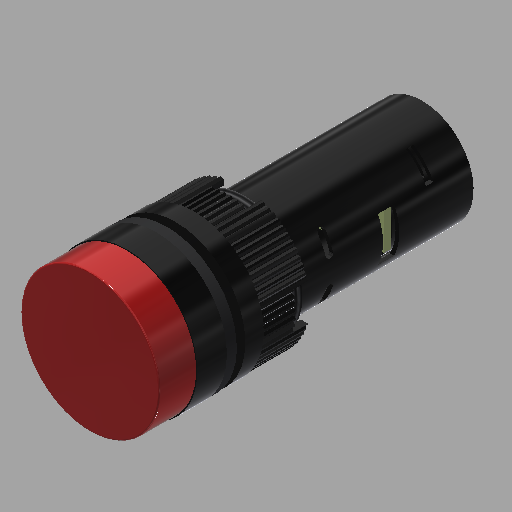
# Autodesk Inventor part: SINALEIRO VERMELHO
Saved by Autodesk Inventor 2022.2 (Build 262287030, 287C)
## iProperties
Created: 2020-08-06
Part Number: SINALEIRO VERMELHO
Material: Plástico, preto opaco
Document SubType Name: Modeling
Designer: Projeto
Density: 0.952 g/cm^3
Appearance: Transparente - Vermelho polido
Mass: 6.60714 g
Surface Area: 62.6153 cm^2
Volume: 6.94027 cm^3
Author: Projeto
Autodesk Inventor part; units mm, degrees
ref_plane "YZ Plane" through (0, 0, 0) normal (1, 0, 0) x (0, 1, 0)
ref_plane "XZ Plane" through (0, 0, 0) normal (0, 1, 0) x (-1, 0, 0)
ref_plane "XY Plane" through (0, 0, 0) normal (0, 0, 1) x (1, 0, 0)
sketch "Esboço1" plane through (0, 0, 0) normal (1, 0, 0) x (0, 1, 0)
  line L0 (0, 0) -> (9.2, 0)
  line L1 (9.4, -0.2) -> (9.4, -5)
  line L2 (9.4, -5) -> (9.55, -5)
  line L3 (9.55, -5) -> (9.55, -9)
  line L4 (9.55, -9) -> (9.5, -9)
  line L5 (9.5, -9) -> (9.5, -10.4)
  line L6 (9.5, -10.4) -> (7.9, -10.4)
  line L7 (7.9, -10.4) -> (7.9, -11.6)
  line L8 (7.9, -11.6) -> (9.45, -11.6)
  line L9 (9.45, -11.6) -> (9.45, -14.1)
  line L10 (9.45, -14.1) -> (9.3, -14.1)
  line L11 (9.3, -14.1) -> (9.3, -20.6)
  line L12 (7, -21.7) -> (7, -43.5)
  line L13 (7, -43.5) -> (6.975, -43.5)
  line L14 (6.975, -43.5) -> (6.975, -45)
  line L15 (6.975, -45) -> (0, -45)
  arc A0 (9.4, -0.2) -> (9.2, 0) centre (9.2, -0.2) ccw
  line L16 (8.35, -20.6) -> (8.35, -18.1)
  line L17 (8.35, -18.1) -> (7.9, -18.1)
  line L18 (7.9, -18.1) -> (7.9, -21.7)
  line L19 (9.3, -20.6) -> (8.35, -20.6)
  line L20 (7.9, -21.7) -> (7, -21.7)
  line L21 (0, -1.5) -> (7.7, -1.5)
  line L22 (7.7, -1.5) -> (7.7, -8.5)
  line L23 (7.7, -8.5) -> (7.35, -8.5)
  line L24 (7.35, -8.5) -> (7.35, -2)
  line L25 (7.35, -2) -> (0, -2)
  line L26 (0, -1.5) -> (0, 0)
  line L27 (0, -21.7) -> (6.5, -21.7)
  line L28 (6.5, -21.7) -> (6.5, -44.5)
  line L29 (6.5, -44.5) -> (6.4, -44.5)
  line L30 (6, -44.1) -> (6, -35)
  line L31 (6, -35) -> (0, -35)
  line L32 (0, 0) -> (0, -45) construction
  line L33 (0, -2) -> (0, -21.7)
  line L34 (0, -35) -> (0, -45)
  line L35 (6.4, -44.5) -> (6, -44.1)
  point P0 (6, -44.5)
  dimension "d8" = 45
  dimension "d9" = 5
  dimension "d10" = 4
  dimension "d11" = 1.4
  dimension "d12" = 1.2
  dimension "d13" = 2.5
  dimension "d15" = 1.5
  dimension "d16" = 0.2
  dimension "d25" = 6.5
  dimension "d26" = 2.5
  dimension "d28" = 1.5
  dimension "d30" = 3
  dimension "d31" = 6.5
  dimension "d32" = 12.7
  dimension "d62" = 14
  dimension "d63" = 13.95
  dimension "d64" = 15.8
  dimension "d65" = 16.7
  dimension "d66" = 18.6
  dimension "d67" = 18.9
  dimension "d68" = 15.8
  dimension "d69" = 19
  dimension "d70" = 19.1
  dimension "d71" = 18.8
  dimension "d72" = 15.4
  dimension "d73" = 14.7
  dimension "d74" = 0.5
  dimension "d75" = 0.5
  dimension "d76" = 12
  dimension "d77" = 10
  dimension "d78" = 0.4
  dimension "d79" = 0.4
  constraints: 72 end point, 30 perpendicular, 6 point on line, 3 vertical, 2 collinear, 2 horizontal, 2 point on circle, 2 tangent, 1 centre point, 1 horizontal alignment
  measures "d8" distance between parallel lines of L0 L15
  measures "d9" distance between parallel lines of L2 L0
  measures "d10" distance of L2.end L3.end
  measures "d11" distance between parallel lines of L4 L6
  measures "d12" distance between parallel lines of L8 L6
  measures "d13" distance of L8.end L9.end
  measures "d15" distance between parallel lines of L13 L15
  measures "d16" radius of A0
  measures "d25" distance between parallel lines of L19 L10
  measures "d26" distance between parallel lines of L17 L19
  measures "d28" distance between parallel lines of L21 L0
  measures "d30" distance between parallel lines of L2 L25
  measures "d31" distance between parallel lines of L23 L25
  measures "d32" distance between parallel lines of L20 L4
  measures "d62" diameter of L12 L32
  measures "d63" diameter of L14 L32
  measures "d64" diameter of L18 L32
  measures "d65" diameter of L16 L32
  measures "d66" diameter of L11 L32
  measures "d67" diameter of L9 L32
  measures "d68" diameter of L7 L32
  measures "d69" diameter of L5 L32
  measures "d70" diameter of L3 L32
  measures "d71" diameter of L1 L32
  measures "d72" diameter of L22 L32
  measures "d73" diameter of L24 L32
  measures "d74" distance between parallel lines of L28 L12
  measures "d75" distance between parallel lines of L15 L29
  measures "d76" diameter of L30 L32
  measures "d77" distance between parallel lines of L15 L31
  measures "d78" distance of L29.end point (6, -44.5)
  measures "d79" distance of L30.start point (6, -44.5)
revolve "Revolução1" add sketch "Esboço1" angle 360 about axis through (0, 0, 0) along (0, 0, -1)
sketch "Esboço3" plane through (0, 0, -20.6) normal (0, 0, -1) x (-1, 0, 0)
  circle A0 centre (0, 0) radius 9.3 projected
  circle A1 centre (0, 0) radius 8.35 projected
  line L0 (-8.9577, -2.5) -> (-7.967, -2.5)
  line L1 (-8.9577, 2.5) -> (-7.967, 2.5)
  line L2 (7.967, -2.5) -> (8.9577, -2.5)
  line L3 (7.967, 2.5) -> (8.9577, 2.5)
  line L4 (-2.5, 7.967) -> (-2.5, 8.9577)
  line L5 (2.5, 7.967) -> (2.5, 8.9577)
  line L6 (-2.5, -7.967) -> (-2.5, -8.9577)
  line L7 (2.5, -7.967) -> (2.5, -8.9577)
  dimension "d33" = 2.5
  dimension "d34" = 2.5
  dimension "d35" = 2.5
  dimension "d36" = 2.5
  constraints: 16 end point, 5 parallel, 2 horizontal, 2 horizontal alignment, 2 vertical alignment, 1 perpendicular, 18 other
  measures "d33" distance from line of point (0, 0) L0
  measures "d34" distance from line of point (0, 0) L1
  measures "d35" distance from line of point (0, 0) L6
  measures "d36" distance from line of point (0, 0) L7
extrude "Extrusão2" cut sketch "Esboço3" against normal blind 2 contours A0 L2 A1 L3 | L5 A1 L4 A0 | A0 L6 A1 L7 | L1 A1 L0 A0
sketch "Esboço4" plane through (8.9577, 2.5, -20.6) normal (0, 0, -1) x (-1, 0, 0)
  arc A0 (11.4577, 6.4577) -> (6.4577, 6.4577) centre (8.9577, -2.5) ccw construction
  line L0 (8.6624, 6.7953) -> (8.887, 6.5707)
  line L1 (9.0284, 6.5707) -> (9.253, 6.7953)
  line L2 (8.9577, 6.5) -> (8.9577, -2.5) construction
  arc A1 (9.253, 6.7953) -> (8.6624, 6.7953) centre (8.9577, -2.5) ccw
  arc A2 (8.887, 6.5707) -> (9.0284, 6.5707) centre (8.9577, 6.6414) ccw
  dimension "d39" = 90
  dimension "d40" = 45
  dimension "d41" = 9
  dimension "d47" = 0.1
  constraints: 6 end point, 6 point on circle, 2 centre point, 2 point on line, 2 tangent, 1 concentric, 1 vertical, 1 vertical alignment
  measures "d39" angle of L1 L0
  measures "d40" angle of L2 L0
  measures "d41" distance of L2.start L2.end
  measures "d47" radius of A2
extrude "Extrusão3" cut sketch "Esboço4" against normal up to surface (6.5 mm away)
pattern_circular "Padrão circular1" count 70 over 360 about axis through (0, 0, -10) along (0, 0, 1) of "Extrusão3"
thread "Rosca1" size "M16x0.75" class "6g" standard "ANSI Metric M Profile" full length
chamfer "Chanfro1" distance 0.8 angle 45 1 edges at (0, -7.9, -21.7)
sketch "Esboço5" plane through (0, 0, -45) normal (0, 0, -1) x (-1, 0, 0)
  point P0 (0, 0)
  point P1 (-3.5, 0)
  point P2 (3.5, 0)
  dimension "d53" = 7
  dimension "d54" = 3.5
  constraints: 2 horizontal alignment
  measures "d53" distance of point (3.5, 0) point (-3.5, 0)
  measures "d54" distance of point (-3.5, 0) point (0, 0)
hole "Furo1" at (3.5, 0, -45) at (-3.5, 0, -45) direction (0, 0, 1) diameter 4.3 depth 9 countersink diameter 5.5 countersink angle 90
sketch "Esboço6" plane through (0, 0, 0) normal (1, 0, 0) x (0, 1, 0)
  line L0 (4.5, -25.7) -> (1.5, -25.7) construction
  line L1 (4, -25.2) -> (2, -25.2)
  line L2 (2, -26.2) -> (4, -26.2)
  arc A0 (4, -26.2) -> (4, -25.2) centre (4, -25.7) ccw
  arc A1 (2, -25.2) -> (2, -26.2) centre (2, -25.7) ccw
  line L3 (-1.5, -25.7) -> (-4.5, -25.7) construction
  line L4 (-2, -25.2) -> (-4, -25.2)
  line L5 (-4, -26.2) -> (-2, -26.2)
  arc A2 (-2, -26.2) -> (-2, -25.2) centre (-2, -25.7) ccw
  arc A3 (-4, -25.2) -> (-4, -26.2) centre (-4, -25.7) ccw
  line L6 (3, -32.7) -> (-3, -32.7)
  line L7 (-3, -32.7) -> (-3, -34.9)
  line L8 (-3, -34.9) -> (3, -34.9)
  line L9 (3, -34.9) -> (3, -32.7)
  line L10 (3, -32.7) -> (-3, -34.9) construction
  line L11 (-3, -32.7) -> (3, -34.9) construction
  line L12 (-6.5, -21.7) -> (6.5, -21.7) projected
  line L13 (6, -39.2) -> (3, -39.2)
  line L14 (3, -39.2) -> (3, -40.2)
  line L15 (3, -40.2) -> (6, -40.2)
  line L16 (6, -40.2) -> (6, -39.2)
  line L17 (6, -39.2) -> (3, -40.2) construction
  line L18 (3, -39.2) -> (6, -40.2) construction
  point P0 (0, 0)
  point P1 (3, -25.7)
  point P2 (-3, -25.7)
  point P3 (0, -33.8)
  point P4 (0, -33.8)
  point P5 (4.5, -39.7)
  dimension "d80" = 3
  dimension "d81" = 1
  dimension "d82" = 1.5
  dimension "d83" = 1.5
  dimension "d84" = 4
  dimension "d85" = 2.2
  dimension "d86" = 6
  dimension "d87" = 11
  dimension "d88" = 3
  dimension "d89" = 1
  dimension "d90" = 17.5
  constraints: 40 end point, 12 point on circle, 8 tangent, 7 midpoint, 6 parallel, 6 point on line, 4 centre point, 3 horizontal, 2 perpendicular, 2 vertical alignment, 1 collinear, 1 equal radius, 1 horizontal alignment
  measures "d80" distance of L0.end L0.start
  measures "d81" distance between parallel lines of L2 L1
  measures "d82" horizontal distance of L0.end point (0, 0)
  measures "d83" horizontal distance of point (0, 0) L3.start
  measures "d84" distance between parallel lines of L0 L12
  measures "d85" distance of L8.end L6.start
  measures "d86" distance of L7.end L8.end
  measures "d87" distance between parallel lines of L6 L12
  measures "d88" distance of L14.end L15.end
  measures "d89" distance of L15.end L13.start
  measures "d90" distance between parallel lines of L12 L13
extrude "Extrusão4" cut sketch "Esboço6" along normal through all
sketch "Esboço7" plane through (3.5, 0, -36) normal (0, 0, -1) x (-1, 0, 0)
  circle A0 centre (0, 0) radius 2.15 projected
  circle A1 centre (0, 0) radius 1.9
  point P0 (3.5, 0)
  dimension "d93" = 3.8
  constraints: 1 centre point, 1 coincident
  measures "d93" diameter of A1
extrude "Extrusão5" add sketch "Esboço7" along normal blind 1 contours A1
sketch "Esboço8" plane through (3.5, 0, -37) normal (0, 0, -1) x (-1, 0, 0)
  circle A0 centre (0, 0) radius 1.9 projected
  point P0 (3.5, 0)
  constraints: 1 coincident
hole "Furo2" at (3.5, 0, -37) direction (0, 0, 1) diameter 1.5 depth 0.5 tip angle 118
chamfer "Chanfro2" distance 0.5 angle 45 1 edges at (3.5, -0.75, -37)
sketch "Esboço9" plane through (3.5, 0, -37) normal (0, 0, -1) x (-1, 0, 0)
  circle A0 centre (0, 0) radius 1.9 projected
  line L0 (-0.3, 2) -> (0.3, 2)
  line L1 (0.3, 2) -> (0.3, -2)
  line L2 (0.3, -2) -> (-0.3, -2)
  line L3 (-0.3, -2) -> (-0.3, 2)
  line L4 (-2, 0.3) -> (2, 0.3)
  line L5 (2, 0.3) -> (2, -0.3)
  line L6 (2, -0.3) -> (-2, -0.3)
  line L7 (-2, -0.3) -> (-2, 0.3)
  point P0 (3.5, 0)
  point P1 (0, 2)
  point P2 (-2, 0)
  point P3 (-0.3, 0)
  point P4 (0, 0.3)
  dimension "d103" = 0.6
  dimension "d106" = 4
  dimension "d107" = 0.6
  dimension "d109" = 4
  constraints: 16 end point, 4 midpoint, 4 parallel, 2 horizontal, 2 horizontal alignment, 2 perpendicular, 2 vertical alignment
  measures "d103" distance of L0.start L0.end
  measures "d106" distance of L2.end L0.start
  measures "d107" distance between parallel lines of L6 L4
  measures "d109" distance of L4.start L4.end
extrude "Extrusão6" cut sketch "Esboço9" against normal blind 0.5 contours A0 L6 L1 L4 | A0 L4 L5 L6 | L1 L4 L3 A0 | A0 L3 L0 L1 | L1 L6 L3 L4 | L1 L2 L3 A0 | A0 L3 L6 L1 | L3 L6 A0 L4 | A0 L6 L7 L4
pattern_circular "Padrão circular2" count 2 over 360 about axis through (0, 0, -10) along (0, 0, 1) of "Extrusão4", "Extrusão5", "Furo2", "Chanfro2", "Extrusão6"
sketch "Esboço10" plane through (0, 0, -35) normal (0, 0, 1) x (1, 0, 0)
  line L0 (5.8, -2.5) -> (-5.8, -2.5)
  line L1 (-5.8, -2.5) -> (-5.8, 2.5)
  line L2 (-5.8, 2.5) -> (5.8, 2.5)
  line L3 (5.8, 2.5) -> (5.8, -2.5)
  line L4 (5.8, -2.5) -> (-5.8, 2.5) construction
  line L5 (-5.8, -2.5) -> (5.8, 2.5) construction
  point P0 (0, 0)
  dimension "d119" = 11.6
  dimension "d120" = 5
  constraints: 12 end point, 2 midpoint, 2 parallel, 1 horizontal, 1 perpendicular
  measures "d119" distance of L1.end L2.end
  measures "d120" distance of L0.end L1.end
extrude "Extrusão7" add sketch "Esboço10" along normal blind 2.5
sketch "Esboço11" plane through (5.8, 1.5362, -35) normal (1, 0, 0) x (0, 0, -1)
  line L0 (0, 0.9638) -> (0, 0) projected
  line L1 (0, 0.9638) -> (-2.5, 0.9638) projected
  line L2 (-2.5, -4.0362) -> (-2.5, 0.9638) projected
  line L3 (0, -4.0362) -> (-2.5, -4.0362) projected
  line L4 (0, -3.0725) -> (0, -4.0362) projected
  line L5 (0, 0) -> (0, -3.0725) projected
  line L6 (-1.8, -4.0362) -> (-1, -4.0362)
  line L7 (-1, -4.0362) -> (-1, 0.9638)
  line L8 (-1, 0.9638) -> (-1.8, 0.9638)
  line L9 (-1.8, 0.9638) -> (-1.8, -4.0362)
  point P0 (-35, -1.5362)
  dimension "d123" = 0.8
  dimension "d124" = 0.7
  constraints: 8 end point, 2 parallel, 2 point on line, 1 horizontal, 1 perpendicular
  measures "d123" distance between parallel lines of L7 L9
  measures "d124" distance between parallel lines of L9 L2
extrude "Extrusão8" cut sketch "Esboço11" against normal up to surface (11.6 mm away) contours L7 L3 L9 L1
equation "\"d79\" = d78"
equation "\"d34\" = d33"
equation "\"d83\" = d82"
equation "\"d107\" = d103"
